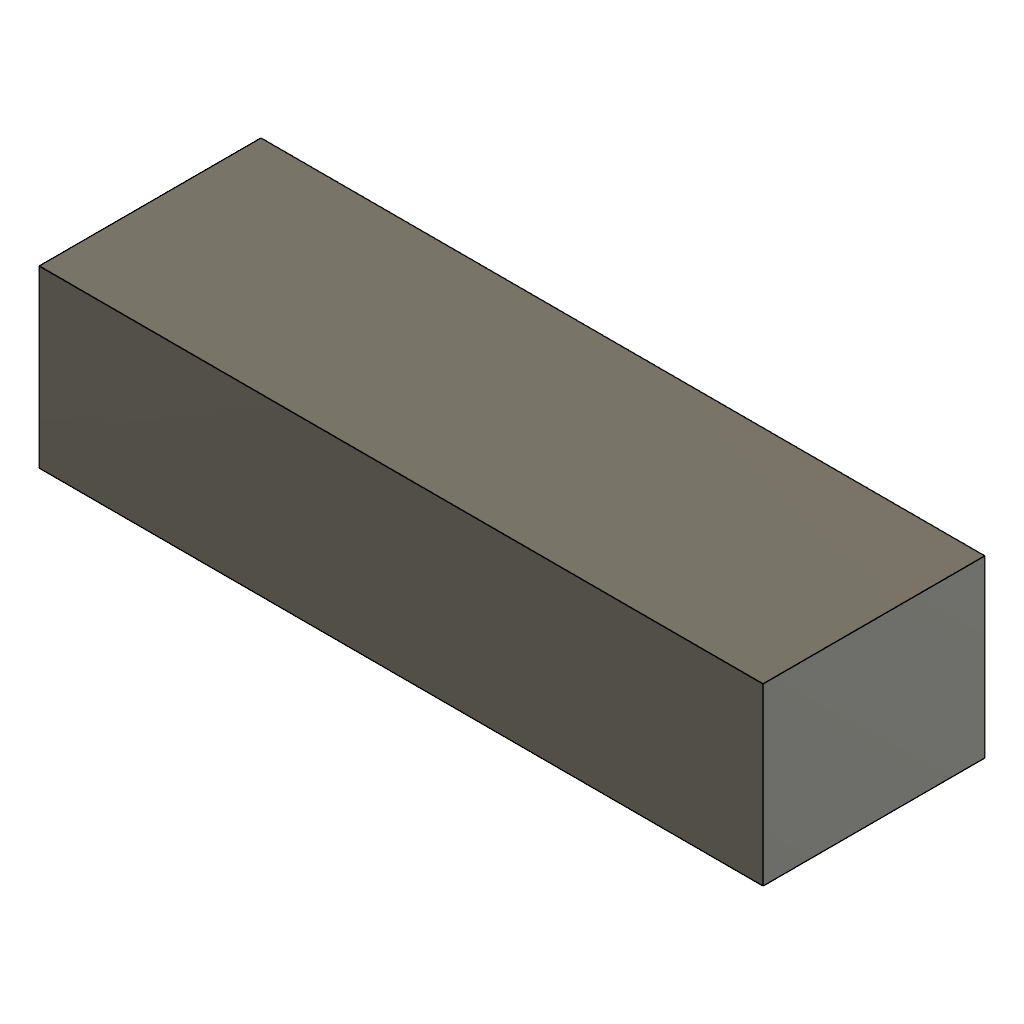
FluffelDrone_v1_Brushed (Autodesk Fusion 360 archive; units mm, degrees)
design "FluffelDrone-v1-Battery-Pack"
part number: 2026-11-22-13-46-37-044
Autodesk Fusion 360 part; units mm, degrees
sketch "Skizze1" plane through (0, 0, 0) normal (0, 1, 0) x (1, 0, 0)
  line L0 (0, 0) -> (62, 0)
  line L1 (62, 0) -> (62, -19)
  line L2 (62, -19) -> (0, -19)
  line L3 (0, -19) -> (0, 0)
  dimension "d1" = 62
  dimension "d2" = 19
  constraint horizontal L0
  constraint vertical L1
  constraint horizontal L2
  constraint vertical L3
  constraint coincident L0.start L3.end
  measures "d1" distance of L0.start L0.end
  measures "d2" distance of L0.start L2.end
extrude "Extrusion1" add sketch "Skizze1" along normal blind 15

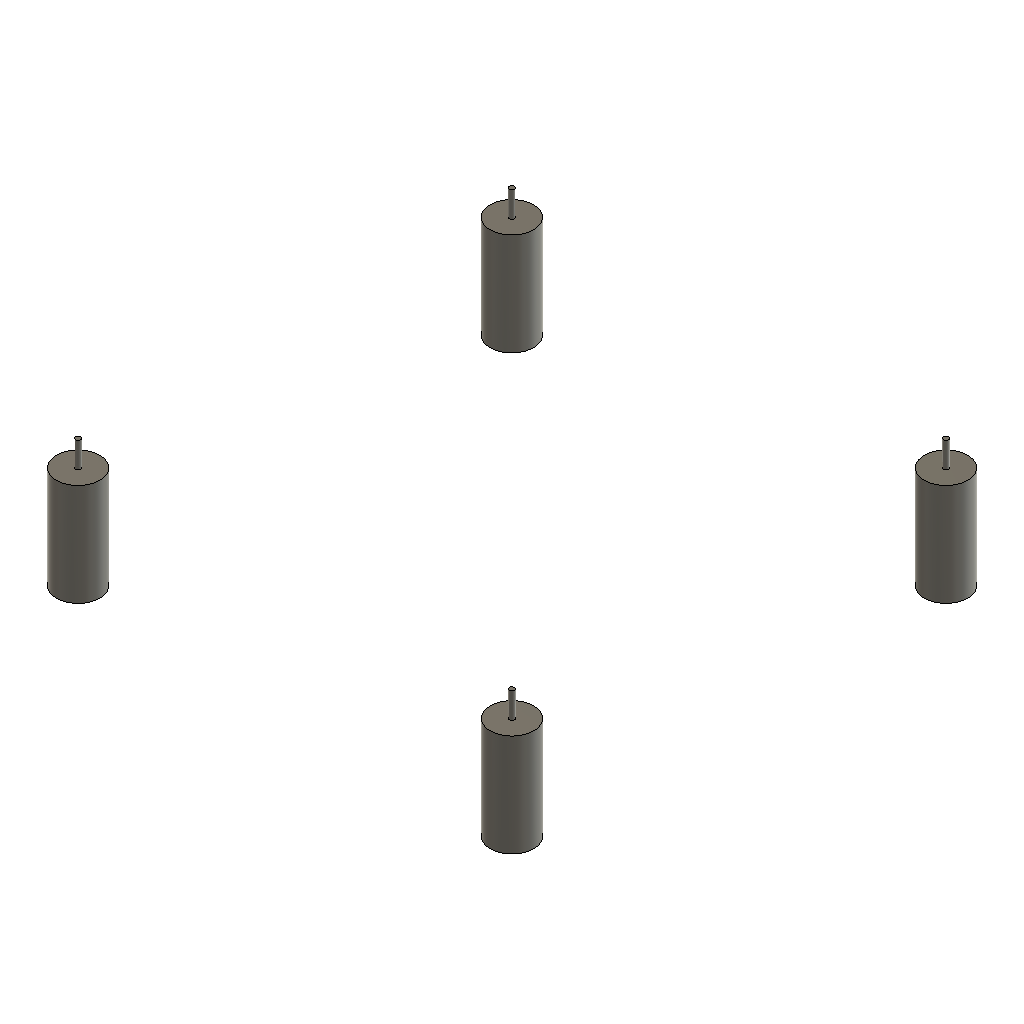
design "FluffelDron-v1-Motors"
part number: 2026-11-22-14-11-26-822
Autodesk Fusion 360 part; units mm, degrees
sketch "Skizze1" plane through (0, 0, 0) normal (0, 1, 0) x (1, 0, 0)
  circle A0 centre (0, 0) radius 4.25
  dimension "d1" = 8.5
  constraint coincident A0.centre origin
  measures "d1" diameter of A0
extrude "Extrusion1" add sketch "Skizze1" along normal blind 20 makes body 1
sketch "Skizze2" plane through (0, 20, 0) normal (0, 1, 0) x (-1, 0, 0)
  circle A0 centre (0, 0) radius 4.25
  circle A1 centre (0, 0) radius 0.5
  dimension "d4" = 1
  constraint coincident A0.centre A1.centre
  measures "d4" diameter of A1
extrude "Extrusion2" add sketch "Skizze2" along normal blind 5 contours A1 bodies 1
copy_body "Körper kopieren/einfügen1" bodies 1 makes body 2
move_body "Verschieben1" bodies 2 to x (1, 0, 0) y (0, 1, 0) z (0, 0, 1) at (10, 0, 0)
copy_body "Körper kopieren/einfügen2" bodies 2 1 makes body 3 makes body 4
move_body "Verschieben2" bodies 3 4 to x (1, 0, 0) y (0, 1, 0) z (0, 0, 1) at (0, 0, 10)
move_body "Verschieben3" bodies 2 to x (1, 0, 0) y (0, 1, 0) z (0, 0, 1) at (-27.0146, 0, 83.0155)
move_body "Verschieben4" bodies 2 to x (1, 0, 0) y (0, 1, 0) z (0, 0, 1) at (0, 1, 0)
move_body "Verschieben5" bodies 3 to x (1, 0, 0) y (0, 1, 0) z (0, 0, 1) at (58.0045, -9, 72.9938)
move_body "Verschieben6" bodies 3 to x (1, 0, 0) y (0, 1, 0) z (0, 0, 1) at (0, 10, 0)
move_body "Verschieben7" bodies 4 to x (1, 0, 0) y (0, 1, 0) z (0, 0, 1) at (-16.9903, 0, 157.989)
move_body "Verschieben8" bodies 4 to x (1, 0, 0) y (0, 1, 0) z (0, 0, 1) at (0, 1, 0)
move_body "Verschieben9" bodies 1 to x (1, 0, 0) y (0, 1, 0) z (0, 0, 1) at (67.9985, 0, 167.9949)
move_body "Verschieben10" bodies 1 to x (1, 0, 0) y (0, 1, 0) z (0, 0, 1) at (0, 1, 0)
